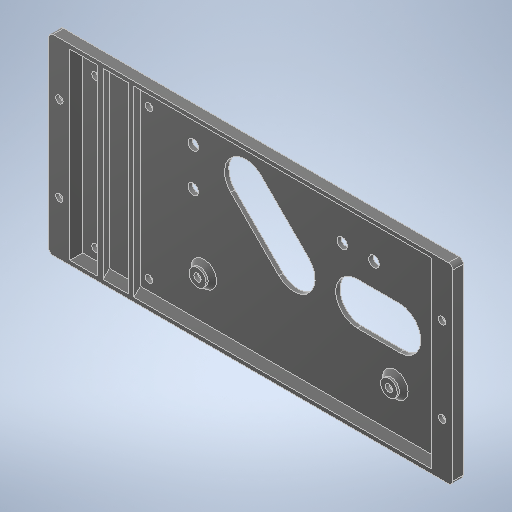
# Autodesk Inventor part: 3D_plate-fix
Saved by Autodesk Inventor 2025.3 (Build 293356030, 356C)
## iProperties
Created: 2025-09-04
Part Number: 3D_plate-fix
Material: 一般
Document SubType Name: Modeling
Designer: ibuki_ono
Density: 1 g/cm^3
Appearance: 滑らか - 黒
Author: ibuki_ono
## iProperties of the stored document 3D_plate-fix_3D プリント.ipt
Created: 2025-09-04
Part Number: 3D_plate-fix_3D プリント
Material: 一般
Document SubType Name: Modeling
Designer: ibuki_ono
Density: 1 g/cm^3
Appearance: 既定
Author: ibuki_ono
Autodesk Inventor part; units mm, degrees
ref_plane "YZ Plane" through (0, 0, 0) normal (1, 0, 0) x (0, 1, 0)
ref_plane "XZ Plane" through (0, 0, 0) normal (0, 1, 0) x (-1, 0, 0)
sketch "スケッチ1" plane through (0, 0, 0) normal (0, 0, 1) x (1, 0, 0)
  line L0 (-95, -45) -> (95, -45)
  line L1 (95, -45) -> (95, 45)
  line L2 (95, 45) -> (-95, 45)
  line L3 (-95, 45) -> (-95, -45)
  line L4 (-95, -45) -> (95, 45) construction
  line L5 (95, -45) -> (-95, 45) construction
  point P0 (0, 0)
  dimension "d0" = 190
  dimension "d1" = 90
  constraints: 12 end point, 2 midpoint, 2 parallel, 1 horizontal, 1 perpendicular
  measures "d0" distance of L2.end L1.end
  measures "d1" distance of L1.end L0.end
extrude "押し出し1" add sketch "スケッチ1" along normal blind 2
sketch "スケッチ2" plane through (0, 0, 2) normal (0, 0, 1) x (1, 0, 0)
  line L0 (95, -45) -> (95, 45) projected
  line L1 (95, 45) -> (-95, 45) projected
  line L2 (-95, 45) -> (-95, -45) projected
  line L3 (-95, -45) -> (95, -45) projected
  line L4 (-95, -45) -> (95, -45) projected
  line L5 (-95, 45) -> (-85, 45)
  line L6 (-85, 45) -> (-85, -45)
  line L7 (-85, -45) -> (-95, -45)
  line L8 (-95, -45) -> (-95, 45)
  point P0 (0, 0)
  dimension "d4" = 10
  constraints: 8 end point, 2 parallel, 1 horizontal, 1 perpendicular, 1 point on line
  measures "d4" distance of L6.end L7.end
extrude "押し出し2" add sketch "スケッチ2" along normal blind 3 contours L3 L2 L1 L6
sketch "スケッチ3" plane through (0, 0, 5) normal (0, 0, 1) x (1, 0, 0)
  line L0 (-85, 45) -> (-95, 45) projected
  line L1 (-95, -45) -> (-85, -45) projected
  line L2 (-90, 45) -> (-90, -45) construction
  point P0 (0, 0)
  point P1 (-90, 20)
  point P2 (-90, -20)
  dimension "d7" = 20
  dimension "d8" = 20
  constraints: 2 end point, 2 midpoint, 2 point on line
  measures "d7" vertical distance of point (0, 0) point (-90, 20)
  measures "d8" vertical distance of point (0, 0) point (-90, -20)
hole "穴1" at (-90, 20, 5) at (-90, -20, 5) direction (0, 0, -1) diameter 3.5 end through all
sketch "スケッチ4" plane through (0, 0, 0) normal (0, 0, -1) x (-1, 0, 0)
  circle A0 centre (90, 20) radius 1.75 projected
  circle A1 centre (90, -20) radius 1.75 projected
  line L0 (90, 23.1754) -> (92.75, 21.5877)
  line L1 (92.75, 21.5877) -> (92.75, 18.4123)
  line L2 (92.75, 18.4123) -> (90, 16.8246)
  line L3 (90, 16.8246) -> (87.25, 18.4123)
  line L4 (87.25, 18.4123) -> (87.25, 21.5877)
  line L5 (87.25, 21.5877) -> (90, 23.1754)
  line L6 (90, -16.8246) -> (92.75, -18.4123)
  line L7 (92.75, -18.4123) -> (92.75, -21.5877)
  line L8 (92.75, -21.5877) -> (90, -23.1754)
  line L9 (90, -23.1754) -> (87.25, -21.5877)
  line L10 (87.25, -21.5877) -> (87.25, -18.4123)
  line L11 (87.25, -18.4123) -> (90, -16.8246)
  point P0 (0, 0)
  dimension "d16" = 5.5
  dimension "d17" = 5.5
  constraints: 24 end point, 2 coincident, 2 vertical alignment, 26 other
  measures "d16" distance between parallel lines of L1 L4
  measures "d17" distance between parallel lines of L7 L10
extrude "押し出し3" cut sketch "スケッチ4" against normal blind 3 contours A1 | L0 L1 L2 L3 L4 L5 | L6 L7 L8 L9 L10 L11
sketch "スケッチ5" plane through (0, 0, 3) normal (0, 0, -1) x (-1, 0, 0)
  circle A0 centre (90, -20) radius 1.75 projected
  line L0 (87.25, -21.5877) -> (87.25, -18.4123) projected
  line L1 (90, -23.1754) -> (87.25, -21.5877) projected
  line L2 (92.75, -21.5877) -> (90, -23.1754) projected
  line L3 (92.75, -18.4123) -> (92.75, -21.5877) projected
  line L4 (90, -16.8246) -> (92.75, -18.4123) projected
  line L5 (87.25, -18.4123) -> (90, -16.8246) projected
  line L6 (87.25, 18.4123) -> (87.25, 21.5877) projected
  line L7 (90, 16.8246) -> (87.25, 18.4123) projected
  line L8 (92.75, 18.4123) -> (90, 16.8246) projected
  line L9 (92.75, 21.5877) -> (92.75, 18.4123) projected
  line L10 (90, 23.1754) -> (92.75, 21.5877) projected
  line L11 (87.25, 21.5877) -> (90, 23.1754) projected
  circle A1 centre (90, 20) radius 1.75 projected
  line L12 (91.75, 22.1651) -> (91.75, 17.8349)
  line L13 (91, 17.4019) -> (87.25, 19.567)
  line L14 (87.25, 20.433) -> (91, 22.5981)
  line L15 (91.75, -17.8349) -> (91.75, -22.1651)
  line L16 (91, -22.5981) -> (87.25, -20.433)
  line L17 (87.25, -19.567) -> (91, -17.4019)
  line L18 (87.25, -18.4123) -> (90, -16.8246) projected
  line L19 (92.75, -18.4123) -> (92.75, -21.5877) projected
  line L20 (90, -23.1754) -> (87.25, -21.5877) projected
  line L21 (87.25, -21.5877) -> (87.25, -18.4123) projected
  line L22 (90, 16.8246) -> (87.25, 18.4123) projected
  line L23 (87.25, 21.5877) -> (90, 23.1754) projected
  line L24 (92.75, 21.5877) -> (92.75, 18.4123) projected
  circle A2 centre (90, 20) radius 1.75 projected
  circle A3 centre (90, -20) radius 1.75 projected
  point P0 (0, 0)
  point P1 (89.125, -18.4845)
  point P2 (89.125, -21.5155)
  point P3 (91.75, -20)
  point P4 (89.125, 18.4845)
  point P5 (91.75, 20)
  point P6 (89.125, 21.5155)
  constraints: 14 point on line, 12 end point, 7 parallel, 5 tangent, 1 vertical
extrude "押し出し4" cut sketch "スケッチ5" against normal blind 0.2 contours L15 L2 L16 A0 | A0 L17 L4 L15 | A0 L16 L0 L17 | L6 L14 A1 L13 | A1 L12 L8 L13 | L14 L10 L12 A1
mirror "ミラー1" about plane through (0, 0, 0) normal (1, 0, 0) of "押し出し2", "穴1", "押し出し3", "押し出し4"
chamfer "面取り1" distance 3 angle 45 2 edges at (85, 0, 2) (-85, 0, 2)
sketch "スケッチ6" plane through (0, 0, 2) normal (0, 0, 1) x (1, 0, 0)
  line L0 (-25, -20) -> (65, -20) construction
  line L1 (-25, -20) -> (65, -20) construction
  circle A0 centre (-25, -20) radius 4
  circle A1 centre (65, -20) radius 4
  line L2 (95, 45) -> (95, -45) projected
  point P0 (0, 0)
  point P1 (20, -20)
  dimension "d25" = 90
  dimension "d26" = 0
  dimension "d27" = 20
  dimension "d28" = 8
  dimension "d29" = 8
  dimension "d50" = 30
  constraints: 4 end point, 2 centre point, 2 coincident, 2 horizontal, 1 collinear, 1 midpoint
  measures "d25" distance of L0.start L0.end
  measures "d26" distance between parallel lines of L0 L1
  measures "d27" distance from line of point (0, 0) L0
  measures "d28" diameter of A0
  measures "d29" diameter of A1
  measures "d50" distance from line of L2 L0.end
extrude "押し出し5" add sketch "スケッチ6" along normal blind 3
sketch "スケッチ7" plane through (65, -20, 5) normal (0, 0, 1) x (1, 0, 0)
  circle A0 centre (-90, 0) radius 4 projected
  circle A1 centre (0, 0) radius 4 projected
  point P0 (-65, 20)
hole "穴2" at (-25, -20, 5) at (65, -20, 5) direction (0, 0, -1) diameter 3.5 end through all
sketch "スケッチ8" plane through (0, 0, 0) normal (0, 0, -1) x (-1, 0, 0)
  circle A0 centre (-65, -20) radius 1.75 projected
  circle A1 centre (-65, -20) radius 4 projected
  line L0 (-61.8246, -20) -> (-63.4123, -22.75)
  line L1 (-63.4123, -22.75) -> (-66.5877, -22.75)
  line L2 (-66.5877, -22.75) -> (-68.1754, -20)
  line L3 (-68.1754, -20) -> (-66.5877, -17.25)
  line L4 (-66.5877, -17.25) -> (-63.4123, -17.25)
  line L5 (-63.4123, -17.25) -> (-61.8246, -20)
  point P0 (0, 0)
  dimension "d39" = 5.5
  constraints: 12 end point, 1 coincident, 1 horizontal alignment, 13 other
  measures "d39" distance between parallel lines of L4 L1
extrude "押し出し6" cut sketch "スケッチ8" against normal blind 3 contours L0 L1 L2 L3 L4 L5
sketch "スケッチ9" plane through (0, 0, 3) normal (0, 0, -1) x (-1, 0, 0)
  line L0 (-66.5877, -17.25) -> (-63.4123, -17.25) projected
  line L1 (-68.1754, -20) -> (-66.5877, -17.25) projected
  line L2 (-66.5877, -22.75) -> (-68.1754, -20) projected
  line L3 (-63.4123, -22.75) -> (-66.5877, -22.75) projected
  line L4 (-61.8246, -20) -> (-63.4123, -22.75) projected
  line L5 (-63.4123, -17.25) -> (-61.8246, -20) projected
  circle A0 centre (-65, -20) radius 1.75 projected
  line L6 (-62.8349, -21.75) -> (-67.1651, -21.75)
  line L7 (-66.5877, -22.75) -> (-68.1754, -20) projected
  line L8 (-67.5981, -21) -> (-65.433, -17.25)
  line L9 (-64.567, -17.25) -> (-62.4019, -21)
  line L10 (-63.4123, -17.25) -> (-61.8246, -20) projected
  line L11 (-63.4123, -22.75) -> (-66.5877, -22.75) projected
  line L12 (-68.1754, -20) -> (-66.5877, -17.25) projected
  circle A1 centre (-65, -20) radius 1.75 projected
  point P0 (0, 0)
  point P1 (-63.4845, -19.125)
  point P2 (-66.5155, -19.125)
  point P3 (-65, -21.75)
  constraints: 6 end point, 6 point on line, 3 parallel, 3 tangent, 1 horizontal
extrude "押し出し7" cut sketch "スケッチ9" against normal blind 0.2 contours L0 L9 A0 L8 | A0 L6 L2 L8 | L9 L4 L6 A0
chamfer "面取り2" distance 2 angle 45 2 edges at (-29, -20, 2) (61, -20, 2)
pattern_linear "矩形状パターン1" count 2 spacing 90 along (-1, 0, 0) of "押し出し7", "押し出し6"
sketch "スケッチ10" plane through (0, 0, 2) normal (0, 0, 1) x (1, 0, 0)
  line L0 (82, 45) -> (-82, 45) projected
  line L1 (-82, -45) -> (82, -45) projected
  line L2 (-69.4, -45) -> (-57.4, -45)
  line L3 (-57.4, -45) -> (-57.4, 45)
  line L4 (-57.4, 45) -> (-69.4, 45)
  line L5 (-69.4, 45) -> (-69.4, -45)
  line L6 (-71.9, -47.5) -> (-54.9, -47.5)
  line L7 (-54.9, -47.5) -> (-54.9, 47.5)
  line L8 (-54.9, 47.5) -> (-71.9, 47.5)
  line L9 (-71.9, 47.5) -> (-71.9, -47.5)
  line L10 (-95, 45) -> (-95, -45) projected
  point P0 (0, 0)
  point P1 (-54.9, -45)
  point P2 (-54.9, 45)
  point P3 (-71.9, 45)
  point P4 (-71.9, -45)
  dimension "d51" = 12
  dimension "d52" = 2.5
  dimension "d53" = 25.6
  constraints: 16 end point, 4 parallel, 2 perpendicular, 2 point on line, 1 horizontal, 3 other
  measures "d51" distance of L4.end L3.end
  measures "d52" distance between parallel lines of L5 L9
  measures "d53" distance between parallel lines of L10 L5
extrude "押し出し8" add sketch "スケッチ10" along normal blind 3 contours L0 L7 L1 L3 | L5 L1 L9 L0
sketch "スケッチ11" plane through (0, 0, 2) normal (0, 0, 1) x (1, 0, 0)
  line L0 (-76, 35) -> (-76, -35) construction
  line L1 (-76, 35) -> (-6, 35) construction
  line L2 (-95, 45) -> (-95, -45) construction
  point P0 (0, 0)
  point P1 (-76, 0)
  point P2 (-95, 0)
  dimension "d56" = 70
  dimension "d57" = 90
  dimension "d58" = 19
  constraints: 4 end point, 2 coincident, 2 midpoint, 1 horizontal, 1 horizontal alignment, 1 perpendicular, 1 vertical
  measures "d56" distance of L0.start L0.end
  measures "d57" angle of L0 L1
  measures "d58" distance between parallel lines of L2 L0
hole "穴3" at (-76, 35, 2) at (-76, -35, 2) direction (0, 0, -1) diameter 3.5 end through all
ref_plane "作業平面1" through (-63.4, -45, 2) normal (-1, 0, 0) x (0, 0, 1)
mirror "ミラー3" about plane through (-63.4, -45, 2) normal (-1, 0, 0) of "穴3"
sketch "スケッチ12" plane through (-95, -45, 0) normal (0, -1, 0) x (1, 0, 0)
  line L0 (10, 5) -> (13, 2) projected
  line L1 (13, 2) -> (23.1, 2) projected
  line L2 (177, 2) -> (180, 5) projected
  line L3 (40.1, 2) -> (177, 2) projected
  line L4 (10, 5) -> (180, 5)
  line L5 (180, 5) -> (180, 2)
  line L6 (180, 2) -> (10, 2)
  line L7 (10, 2) -> (10, 5)
  point P0 (95, 0)
  constraints: 8 end point, 2 parallel, 1 collinear, 1 horizontal, 1 perpendicular
extrude "押し出し9" add sketch "スケッチ12" against normal blind 2 contours L4 L2 L3 L6 L1 L0
mirror "ミラー4" about plane through (0, 0, 0) normal (0, 1, 0) of "押し出し9"
chamfer "面取り3" distance 3 angle 45 6 edges at (-76.95, 43, 2) (-63.4, 43, 2) (13.55, 43, 2) (13.55, -43, 2) (-63.4, -43, 2) (-76.95, -43, 2)
sketch "スケッチ13" plane through (0, 0, 2) normal (0, 0, 1) x (1, 0, 0)
  point P0 (0, 0)
  point P1 (55, 25)
  point P2 (40, 25)
  point P3 (-30, 30)
  point P4 (-30, 12)
  dimension "d71" = 40
  dimension "d72" = 15
  dimension "d73" = 25
  dimension "d74" = 25
  dimension "d75" = 30
  dimension "d76" = 30
  dimension "d77" = 30
  dimension "d78" = 18
  measures "d71" horizontal distance of point (0, 0) point (40, 25)
  measures "d72" distance of point (40, 25) point (55, 25)
  measures "d73" vertical distance of point (0, 0) point (55, 25)
  measures "d74" vertical distance of point (0, 0) point (40, 25)
  measures "d75" horizontal distance of point (0, 0) point (-30, 30)
  measures "d76" horizontal distance of point (0, 0) point (-30, 12)
  measures "d77" horizontal distance of point (0, 0) point (-30, 30)
  measures "d78" distance of point (-30, 12) point (-30, 30)
hole "穴4" at (55, 25, 2) at (40, 25, 2) at (-30, 30, 2) at (-30, 12, 2) direction (0, 0, -1) diameter 5 end through all
sketch "スケッチ14" plane through (0, 0, 2) normal (0, 0, 1) x (1, 0, 0)
  line L0 (-5.3137, 26.5269) -> (17.3137, 3.8995) construction
  line L1 (-12.3848, 19.4558) -> (10.2426, -3.1716)
  line L2 (24.3848, 10.9706) -> (1.7574, 33.598)
  arc A0 (1.7574, 33.598) -> (-12.3848, 19.4558) centre (-5.3137, 26.5269) ccw
  arc A1 (10.2426, -3.1716) -> (24.3848, 10.9706) centre (17.3137, 3.8995) ccw
  line L3 (-95, 45) -> (95, 45) projected
  line L4 (47, 3.8995) -> (67, 3.8995) construction
  line L5 (47, -6.1005) -> (67, -6.1005)
  line L6 (67, 13.8995) -> (47, 13.8995)
  arc A2 (47, 13.8995) -> (47, -6.1005) centre (47, 3.8995) ccw
  arc A3 (67, -6.1005) -> (67, 13.8995) centre (67, 3.8995) ccw
  line L7 (95, 45) -> (95, -45) projected
  point P0 (0, 0)
  point P1 (6, 15.2132)
  point P2 (57, 3.8995)
  dimension "d86" = 15
  dimension "d87" = 10
  dimension "d88" = 32
  dimension "d89" = 6
  dimension "d90" = 45
  dimension "d93" = 10
  dimension "d94" = 20
  dimension "d95" = 28
  constraints: 16 end point, 9 tangent, 8 point on circle, 4 centre point, 2 midpoint, 2 parallel, 1 horizontal
  measures "d86" distance from line of point (0, 0) L0
  measures "d87" radius of A0
  measures "d88" distance of L0.start L0.end
  measures "d89" horizontal distance of point (0, 0) point (6, 15.213)
  measures "d90" angle of L3 L0
  measures "d93" radius of A2
  measures "d94" distance of L4.start L4.end
  measures "d95" distance from line of L7 L4.end
extrude "押し出し10" cut sketch "スケッチ14" against normal through all
fillet "フィレット1" radius 2 4 edges at (-95, -45, 2.5) (-95, 45, 2.5) (95, -45, 2.5) (95, 45, 2.5)
equation "\"d8\" = d7"
equation "\"d17\" = d16"
equation "\"d74\" = d73"
equation "\"d76\" = d75"
equation "\"d93\" = d87"
